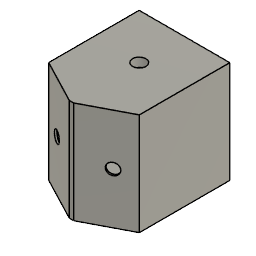
The Box (1) (Autodesk Fusion 360 design; units mm, degrees)
Autodesk Fusion 360 part; units mm, degrees
sketch "Sketch1" plane through (0, 0, 0) normal (0, 1, 0) x (1, 0, 0)
  line L0 (0, 0) -> (203.2, 0)
  line L1 (203.2, 0) -> (203.2, -228.6)
  line L2 (203.2, -228.6) -> (0, -228.6)
  line L3 (0, -228.6) -> (0, 0)
  dimension "d1" = 203.2
  dimension "d2" = 228.6
  constraint horizontal L0
  constraint vertical L1
  constraint horizontal L2
  constraint vertical L3
  constraint coincident L0.start L3.end
  measures "d1" distance of L0.start L0.end
  measures "d2" distance of L0.start L2.end
extrude "Extrude1" add sketch "Sketch1" along normal blind 202.8
sketch "Sketch5" plane through (0, 0, 0) normal (0, -1, 0) x (1, 0, 0)
  line L0 (203.2, 228.6) -> (0, 228.6)
  line L1 (0, 228.6) -> (0, 0)
  line L2 (0, 0) -> (203.2, 0)
  line L3 (203.2, 0) -> (203.2, 228.6)
  line L4 (0, 228.6) -> (71.2, 228.6)
  line L5 (71.2, 228.6) -> (81.2, 228.6)
  line L6 (81.2, 228.6) -> (152.4, 228.6)
  line L7 (71.2, 228.6) -> (81.2, 228.6)
  line L8 (81.2, 228.6) -> (81.2, 0)
  line L9 (81.2, 0) -> (71.2, 0)
  line L10 (71.2, 0) -> (71.2, 228.6)
  dimension "d24" = 71.2
  dimension "d25" = 10
  dimension "d26" = 71.2
  constraint coincident L0.end L1.start
  constraint perpendicular L1 L4
  constraint coincident L0 L5.end
  constraint parallel L0 L6
  constraint horizontal L7
  constraint vertical L8
  constraint horizontal L9
  constraint vertical L10
  constraint coincident L2 L8.end
  measures "d24" distance of L0.end L4.end
  measures "d25" distance of L4.end L5.end
  measures "d26" distance of L5.end L6.end
sketch "Sketch10" plane through (0, 0, 228.6) normal (0, 0, 1) x (-1, 0, 0)
  line L0 (0, 0) -> (-203.2, 0)
  line L1 (-203.2, 0) -> (-203.2, -202.8)
  line L2 (-203.2, -202.8) -> (0, -202.8)
  line L3 (0, -202.8) -> (0, 0)
  line L4 (-4, -198.8) -> (-199.2, -198.8)
  line L5 (-199.2, -198.8) -> (-199.2, -4)
  line L6 (-199.2, -4) -> (-4, -4)
  line L7 (-4, -4) -> (-4, -198.8)
  dimension "d51" = 4
  dimension "d52" = 4
  dimension "d53" = 4
  dimension "d54" = 4
  constraint horizontal L4
  constraint vertical L5
  constraint horizontal L6
  constraint vertical L7
  measures "d51" distance of L3 L7
  measures "d52" distance of L2 L4
  measures "d53" distance of L1 L5
  measures "d54" distance of L0 L6
extrude "Extrude12" cut sketch "Sketch10" against normal blind 190 contours L4 L5 L6 L7
sketch "Sketch17" plane through (0, 0, 0) normal (0, -1, 0) x (1, 0, 0)
  line L0 (203.2, 228.6) -> (0, 228.6)
  line L1 (0, 228.6) -> (0, 0)
  line L2 (0, 0) -> (203.2, 0)
  line L3 (203.2, 0) -> (203.2, 228.6)
extrude "Extrude25" add sketch "Sketch10" against normal blind 20 contours L4 L5 L6 L7
sketch "Sketch18" plane through (0, 202.8, 0) normal (0, 1, 0) x (-1, 0, 0)
  line L0 (0, 228.6) -> (-203.2, 228.6)
  line L1 (-203.2, 228.6) -> (-203.2, 0)
  line L2 (-203.2, 0) -> (0, 0)
  line L3 (0, 0) -> (0, 228.6)
  line L4 (-199.2, 208.6) -> (-4, 208.6)
  line L5 (-4, 208.6) -> (-4, 30)
  line L6 (-4, 30) -> (-199.2, 30)
  line L7 (-199.2, 30) -> (-199.2, 208.6)
  dimension "d88" = 20
  dimension "d128" = 30
  dimension "d129" = 178.6
  constraint horizontal L4
  constraint vertical L5
  constraint horizontal L6
  constraint vertical L7
  measures "d88" distance of L0 L4
  measures "d128" distance of L2 L6
  measures "d129" distance of L4.end L5.end
sketch "Sketch19" plane through (0, 0, 0) normal (0, -1, 0) x (1, 0, 0)
  line L0 (0, 228.6) -> (96.6, 228.6)
  line L1 (96.6, 228.6) -> (106.6, 228.6)
  line L2 (106.6, 228.6) -> (203.2, 228.6)
  line L3 (96.6, 228.6) -> (106.6, 228.6)
  line L4 (106.6, 228.6) -> (106.6, 1.3997)
  line L5 (106.6, 1.3997) -> (96.6, 1.3997)
  line L6 (96.6, 1.3997) -> (96.6, 228.6)
  dimension "d96" = 96.6
  dimension "d97" = 10
  dimension "d98" = 96.6
  constraint horizontal L0
  constraint parallel L0 L1
  constraint parallel L0 L2
  constraint horizontal L3
  constraint vertical L4
  constraint horizontal L5
  constraint vertical L6
  measures "d96" distance of L0.start L0.end
  measures "d97" distance of L0.end L1.end
  measures "d98" distance of L1.end L2.end
extrude "Extrude26" cut sketch "Sketch18" against normal blind 210 contours L4 L5 L6 L7
extrude "Extrude28" add sketch "Sketch19" along normal blind 50.4
sketch "Sketch20" plane through (0, 0, 228.6) normal (0, 0, 1) x (-1, 0, 0)
  line L0 (-106.6, 0) -> (-203.2, 0)
  line L1 (-203.2, 0) -> (-203.2, -202.8)
  line L2 (-203.2, -202.8) -> (0, -202.8)
  line L3 (0, -202.8) -> (0, 0)
  line L4 (0, 0) -> (-96.6, 0)
  line L5 (-96.6, 0) -> (-96.6, 50.4)
  line L6 (-96.6, 50.4) -> (-106.6, 50.4)
  line L7 (-106.6, 50.4) -> (-106.6, 0)
  line L8 (0, 0) -> (-96.6, 50.4)
  line L9 (-106.6, 50.4) -> (-203.2, 0)
  line L10 (0, 0) -> (-96.6, 0)
  line L11 (-96.6, 50.4) -> (-96.6, 0)
  line L12 (-106.6, 50.4) -> (-106.6, 0)
  line L13 (-106.6, 0) -> (-203.2, 0)
  constraint coincident L3.end L4.start
  constraint coincident L5.end L6.start
  constraint coincident L6.end L7.start
  constraint coincident L0.end L1.start
  constraint coincident L4.end L5.start
  constraint coincident L0.start L7.end
extrude "Extrude29" add sketch "Sketch20" against normal blind 228.6 contours L0 L7 L9 L12 L13 | L4 L5 L8 L10 L11
sketch "Sketch21" plane through (43.4782, -83.3331, 0) normal (0.462566, -0.886585, 0) x (0.886585, 0.462566, 0)
  line L0 (180.154, 228.6) -> (71.1966, 228.6)
  line L1 (71.1966, 228.6) -> (71.1966, 1.3997)
  line L2 (71.1966, 1.3997) -> (71.1966, 0)
  line L3 (71.1966, 0) -> (180.154, 0)
  line L4 (180.154, 0) -> (180.154, 228.6)
  line L5 (180.154, 0) -> (180.154, 228.6)
  line L6 (180.154, 228.6) -> (180.154, 114.3)
  line L7 (180.154, 114.3) -> (136.5375, 114.3)
  circle A0 centre (136.5375, 114.3) radius 13
  dimension "d105" = 228.6
  dimension "d106" = 114.3
  dimension "d107" = 43.6165
  dimension "d108" = 26
  constraint coincident L0.start L4.end
  constraint perpendicular L0 L6
  constraint perpendicular L6 L7
  constraint coincident L7.end A0.centre
  measures "d105" distance of L3.end L0.start
  measures "d106" distance of L0.start L6.end
  measures "d107" distance of L6.end L7.end
  measures "d108" diameter of A0
sketch "Sketch22" plane through (0, 0, 0) normal (-0.462566, -0.886585, 0) x (0.886585, -0.462566, 0)
  line L0 (108.9574, 228.6) -> (0, 228.6)
  line L1 (0, 228.6) -> (0, 0)
  line L2 (0, 0) -> (108.9574, 0)
  line L3 (108.9574, 0) -> (108.9574, 1.3997)
  line L4 (108.9574, 1.3997) -> (108.9574, 228.6)
  line L5 (0, 228.6) -> (0, 114.3)
  line L6 (0, 114.3) -> (43.6165, 114.3)
  circle A0 centre (43.6165, 114.3) radius 13
  dimension "d109" = 114.3
  dimension "d110" = 43.6165
  dimension "d111" = 26
  constraint coincident L0.end L1.start
  constraint perpendicular L0 L5
  constraint perpendicular L5 L6
  constraint coincident L6.end A0.centre
  measures "d109" distance of L0.end L5.end
  measures "d110" distance of L5.end L6.end
  measures "d111" diameter of A0
extrude "Extrude30" cut sketch "Sketch20" against normal blind 190 contours L0 L7 L9 L12 L13 | L4 L5 L8 L10 L11
extrude "Extrude31" add sketch "Sketch22" against normal blind 4
extrude "Extrude32" add sketch "Sketch21" against normal blind 4
sketch "Sketch23" plane through (0, 0, 228.6) normal (0, 0, 1) x (-1, 0, 0)
  line L0 (-106.6, 0) -> (-203.2, 0)
  dimension "d119" = 96.6
  measures "d119" distance of L0.start L0.end
extrude "Extrude33" cut 2 faces at (135.9175, -15.2961, 38.6) (67.2825, -15.2961, 38.6) along direction (0, 0, -1) blind 5
extrude "Extrude34" add 1 faces at (103.2667, -30.5922, 1.3997) along direction (0, 0, -1) blind 1.5
sketch "Sketch24" plane through (0, 0, 228.6) normal (0, 0, 1) x (-1, 0, 0)
  line L0 (-8.65, 0) -> (-96.5997, 45.8885)
  line L1 (-96.5997, 45.8885) -> (-96.5997, 0)
  line L2 (-96.5997, 0) -> (-8.65, 0)
  line L3 (-106.6, 0) -> (-106.6, 45.9)
  line L4 (-106.6, 45.9) -> (-194.55, 0)
  line L5 (-194.55, 0) -> (-106.6, 0)
  constraint vertical L1
  constraint perpendicular L1 L2
  constraint vertical L3
  constraint perpendicular L3 L5
extrude "Extrude35" add sketch "Sketch20" against normal blind 20 contours L4 L5 L8 L10 L11
extrude "Extrude36" add sketch "Sketch24" sketch "Sketch20" against normal blind 20 contours L3 L4 L5 of sketch 2 contours L0 L7 L9 L12 L13
sketch "Sketch25" plane through (0, 0, 228.6) normal (0, 0, 1) x (-1, 0, 0)
  line L0 (-106.6, 50.4) -> (-203.2, 0)
  line L1 (-203.2, 0) -> (-203.2, -202.8)
  line L2 (-203.2, -202.8) -> (0, -202.8)
  line L3 (0, -202.8) -> (0, 0)
  line L4 (0, 0) -> (-96.6, 50.4)
  line L5 (-96.6, 50.4) -> (-106.6, 50.4)
  line L6 (0, 0) -> (-96.6, 0)
  line L7 (-106.6, 0) -> (-203.2, 0)
  line L8 (0, 0) -> (-96.6, 50.4)
  line L9 (-106.6, 50.4) -> (-203.2, 0)
  line L10 (-96.6, 50.4) -> (-106.6, 50.4)
  line L11 (-106.6, 50.4) -> (-106.6, 0)
  line L12 (-96.6, 50.4) -> (-96.6, 0)
  dimension "d130" = 96.6
  dimension "d131" = 96.6
  dimension "d132" = 108.9574
  dimension "d133" = 108.9574
  dimension "d134" = 10
  dimension "d135" = 50.4
  dimension "d136" = 50.4
  measures "d130" distance of L3.end L6.end
  measures "d131" distance of L7.start L0.end
  measures "d132" distance of L3.end L4.end
  measures "d133" distance of L0.start L0.end
  measures "d134" distance of L4.end L0.start
  measures "d135" distance of L0.start L7.start
  measures "d136" distance of L4.end L6.end
sketch "Sketch26" plane through (0, 202.8, 0) normal (0, 1, 0) x (-1, 0, 0)
  line L0 (-4, 208.6) -> (-4, 30)
  line L1 (-4, 30) -> (-199.2, 30)
  line L2 (-199.2, 30) -> (-199.2, 208.6)
  line L3 (-199.2, 208.6) -> (-4, 208.6)
  line L4 (0, 228.6) -> (-203.2, 228.6)
  line L5 (-203.2, 228.6) -> (-203.2, 0)
  line L6 (-203.2, 0) -> (0, 0)
  line L7 (0, 0) -> (0, 228.6)
  line L8 (-4, 208.6) -> (-4, 30)
  dimension "d137" = 4
  measures "d137" distance of L7 L8
sketch "Sketch27" plane through (0, 0, 228.6) normal (0, 0, 1) x (-1, 0, 0)
  line L0 (-106.6, 50.4) -> (-203.2, 0)
  line L1 (-203.2, 0) -> (-203.2, -202.8)
  line L2 (-203.2, -202.8) -> (0, -202.8)
  line L3 (0, -202.8) -> (0, 0)
  line L4 (0, 0) -> (-96.6, 50.4)
  line L5 (-96.6, 50.4) -> (-106.6, 50.4)
  line L6 (-203.2, 0) -> (-203.2, -202.8)
  line L7 (-203.2, -202.8) -> (-203.2, -101.4)
  line L8 (-203.2, -202.8) -> (-201.6, -202.8)
  line L9 (-203.2, -101.4) -> (-101.6, -101.4)
  circle A0 centre (-101.6, -101.4) radius 15
  dimension "d138" = 202.8
  dimension "d139" = 101.4
  dimension "d140" = 203.2
  dimension "d141" = 1.6
  dimension "d142" = 101.6
  dimension "d143" = 30
  dimension "d148" = 202.8
  constraint coincident L1.end L2.start
  constraint perpendicular L2 L7
  constraint perpendicular L1 L8
  constraint perpendicular L7 L9
  constraint coincident L9.end A0.centre
  measures "d138" distance of L0.end L1.end
  measures "d139" distance of L1.end L7.end
  measures "d140" distance of L2.end L1.end
  measures "d141" distance of L1.end L8.end
  measures "d142" distance of L7.end L9.end
  measures "d143" diameter of A0
  measures "d148" distance of L0.end L1.end
extrude "Extrude37" cut sketch "Sketch27" against normal blind 280 contours A0
extrude "Extrude38" cut 2 faces at (135.9175, -15.2961, 33.6) (67.2825, -15.2961, 33.6) along direction (0, 0, -1) blind 5
sketch "Sketch28" plane through (0, 0, 0) normal (0, 0, -1) x (1, 0, 0)
  circle A0 centre (101.6, -101.4) radius 15
  line L0 (106.6, 45.8883) -> (106.6, 0)
  line L1 (106.6, 0) -> (96.6, 0)
  line L2 (96.6, 0) -> (96.6, 45.8883)
  line L3 (96.6, 45.8883) -> (98.4503, 46.8537)
  line L4 (98.4503, 46.8537) -> (96.6, 50.4)
  line L5 (96.6, 50.4) -> (0, 0)
  line L6 (0, 0) -> (0, -202.8)
  line L7 (0, -202.8) -> (203.2, -202.8)
  line L8 (203.2, -202.8) -> (203.2, 0)
  line L9 (203.2, 0) -> (106.6, 50.4)
  line L10 (106.6, 50.4) -> (104.7497, 46.8537)
  line L11 (104.7497, 46.8537) -> (106.6, 45.8883)
  line L12 (10, -190) -> (25, -190)
  line L13 (25, -190) -> (25, -165)
  line L14 (25, -165) -> (10, -165)
  line L15 (10, -165) -> (10, -190)
  dimension "d149" = 15
  dimension "d150" = 25
  constraint horizontal L12
  constraint vertical L13
  constraint horizontal L14
  constraint vertical L15
  measures "d149" distance of L12.start L12.end
  measures "d150" distance of L12.start L14.end
extrude "Extrude39" cut sketch "Sketch28" against normal blind 40 contours L12 L13 L14 L15
